Autodesk Inventor part; units mm, degrees
(part 2 of 2)
  spline S387 degree 2 poles (67.0107, -7.6579) (67.1116, -7.5623) (67.7381, -7.0526) knots 0 0 0 1 1 1
  spline S388 degree 2 poles (77.2373, -9.203) (77.7948, -9.5747) (78.0019, -9.8455) knots 0 0 0 1 1 1
  spline S389 degree 2 poles (78.0019, -9.8455) (78.0974, -9.9623) (78.0974, -10.1163) knots 0 0 0 1 1 1
  spline S390 degree 2 poles (78.0974, -10.1163) (78.0974, -10.2119) (78.0231, -10.2862) knots 0 0 0 1 1 1
  spline S391 degree 2 poles (78.0231, -10.2862) (77.9594, -10.3499) (77.8691, -10.3499) knots 0 0 0 1 1 1
  spline S392 degree 2 poles (77.8691, -10.3499) (77.7257, -10.3499) (77.5665, -10.1588) knots 0 0 0 1 1 1
  spline S393 degree 2 poles (77.5665, -10.1588) (77.3222, -9.8189) (77.0673, -9.6331) knots 0 0 0 1 1 1
  spline S394 degree 2 poles (77.0673, -9.6331) (76.8921, -9.9835) (76.5045, -10.1641) knots 0 0 0 1 1 1
  spline S395 degree 2 poles (76.5045, -10.1641) (76.2072, -10.3021) (75.8726, -10.3021) knots 0 0 0 1 1 1
  spline S396 degree 2 poles (75.8726, -10.3021) (75.3895, -10.3021) (75.0974, -10.0951) knots 0 0 0 1 1 1
  spline S397 degree 2 poles (75.0974, -10.0951) (74.8001, -9.8933) (74.8001, -9.5375) knots 0 0 0 1 1 1
  spline S398 degree 2 poles (74.8001, -9.5375) (74.8001, -9.1658) (75.1877, -8.9588) knots 0 0 0 1 1 1
  spline S399 degree 2 poles (75.1877, -8.9588) (75.4691, -8.8048) (75.7983, -8.8048) knots 0 0 0 1 1 1
  spline S400 degree 2 poles (75.7983, -8.8048) (76.3611, -8.8048) (76.7965, -9.0066) knots 0 0 0 1 1 1
  spline S401 degree 2 poles (76.7965, -9.0066) (76.8974, -8.3641) (76.8974, -7.6897) knots 0 0 0 1 1 1
  spline S402 degree 2 poles (76.8974, -7.6897) (76.8974, -6.7712) (76.6638, -6.2455) knots 0 0 0 1 1 1
  spline S403 degree 2 poles (76.6638, -6.2455) (76.4302, -5.7305) (75.9364, -5.7305) knots 0 0 0 1 1 1
  spline S404 degree 2 poles (75.9364, -5.7305) (75.4744, -5.7305) (74.9063, -6.1924) knots 0 0 0 1 1 1
  spline S405 degree 2 poles (74.9063, -6.1924) (74.1842, -6.7765) (73.1965, -7.865) knots 0 0 0 1 1 1
  spline S406 degree 2 poles (73.1965, -7.865) (73.2019, -8.3057) (73.2231, -9.2349) knots 0 0 0 1 1 1
  spline S407 degree 2 poles (73.2231, -9.2349) (73.239, -9.9358) (73.239, -10.0844) knots 0 0 0 1 1 1
  spline S408 degree 2 poles (73.239, -10.0844) (73.239, -10.8119) (72.9948, -10.8119) knots 0 0 0 1 1 1
  spline S409 degree 2 poles (72.9948, -10.8119) (72.7983, -10.8119) (72.7771, -10.5942) knots 0 0 0 1 1 1
  spline S410 degree 2 poles (72.7771, -10.5942) (72.7346, -10.2756) (72.6178, -10.1163) knots 0 0 0 1 1 1
  spline S411 degree 2 poles (72.6178, -10.1163) (72.278, -9.6437) (71.9647, -9.288) knots 0 0 0 1 1 1
  spline S412 degree 2 poles (71.9647, -9.288) (71.8054, -9.5004) (71.6408, -9.6862) knots 0 0 0 1 1 1
  spline S413 degree 2 poles (71.6408, -9.6862) (71.5505, -9.803) (71.4178, -9.803) knots 0 0 0 1 1 1
  spline S414 degree 2 poles (71.4178, -9.803) (71.2319, -9.803) (71.2319, -9.5641) knots 0 0 0 1 1 1
  spline S415 degree 2 poles (71.2319, -9.5641) (71.2319, -9.442) (71.3753, -9.272) knots 0 0 0 1 1 1
  spline S416 degree 2 poles (71.3753, -9.272) (71.9912, -8.5977) (72.3045, -8.157) knots 0 0 0 1 1 1
  spline S417 degree 2 poles (72.3045, -8.157) (72.6921, -7.6048) (72.8939, -7.0685) knots 0 0 0 1 1 1
  spline S418 degree 2 poles (72.8939, -7.0685) (72.9151, -6.7818) (72.9311, -6.4685) knots 0 0 0 1 1 1
  spline S419 degree 2 poles (72.9311, -6.4685) (72.6231, -6.5906) (72.4744, -6.6809) knots 0 0 0 1 1 1
  spline S420 degree 2 poles (72.4744, -6.6809) (72.2992, -6.7712) (72.2514, -6.8136) knots 0 0 0 1 1 1
  spline S421 degree 2 poles (72.2514, -6.8136) (72.1558, -6.9092) (72.0496, -6.9092) knots 0 0 0 1 1 1
  spline S422 degree 2 poles (72.0496, -6.9092) (71.8744, -6.9092) (71.6939, -6.6968) knots 0 0 0 1 1 1
  spline S423 degree 2 poles (71.6939, -6.6968) (71.4921, -6.4579) (71.4921, -6.3092) knots 0 0 0 1 1 1
  spline S424 degree 2 poles (71.4921, -6.3092) (71.4921, -6.1977) (71.5505, -6.1977) knots 0 0 0 1 1 1
  spline S425 degree 2 poles (71.5505, -6.1977) (71.593, -6.1977) (71.6673, -6.272) knots 0 0 0 1 1 1
  spline S426 degree 2 poles (71.6673, -6.272) (71.8426, -6.4526) (72.0072, -6.4526) knots 0 0 0 1 1 1
  spline S427 degree 2 poles (72.0072, -6.4526) (72.1027, -6.4526) (72.1983, -6.4207) knots 0 0 0 1 1 1
  spline S428 degree 2 poles (72.1983, -6.4207) (72.347, -6.3676) (72.947, -6.1287) knots 0 0 0 1 1 1
  spline S429 degree 2 poles (72.947, -6.1287) (72.947, -5.9747) (72.9629, -5.4437) knots 0 0 0 1 1 1
  spline S430 degree 2 poles (72.9629, -5.4437) (72.9735, -5.1198) (72.9735, -4.9765) knots 0 0 0 1 1 1
  spline S431 degree 2 poles (72.9735, -4.9765) (72.9735, -4.6897) (72.8726, -4.5517) knots 0 0 0 1 1 1
  spline S432 degree 2 poles (72.8726, -4.5517) (72.7771, -4.4296) (72.5275, -4.3234) knots 0 0 0 1 1 1
  spline S433 degree 2 poles (72.5275, -4.3234) (72.4532, -4.2915) (72.4532, -4.2384) knots 0 0 0 1 1 1
  spline S434 degree 2 poles (72.4532, -4.2384) (72.4532, -4.1375) (72.6974, -4.1375) knots 0 0 0 1 1 1
  spline S435 degree 2 poles (72.6974, -4.1375) (72.9257, -4.1375) (73.2284, -4.334) knots 0 0 0 1 1 1
  spline S436 degree 2 poles (73.2284, -4.334) (73.616, -4.5889) (73.616, -4.7588) knots 0 0 0 1 1 1
  spline S437 degree 2 poles (73.616, -4.7588) (73.616, -4.8809) (73.5098, -4.9818) knots 0 0 0 1 1 1
  spline S438 degree 2 poles (73.5098, -4.9818) (73.4355, -5.0561) (73.393, -5.2366) knots 0 0 0 1 1 1
  spline S439 degree 2 poles (73.393, -5.2366) (73.3134, -5.5552) (73.3027, -5.98) knots 0 0 0 1 1 1
  spline S440 degree 2 poles (73.3027, -5.98) (73.3824, -5.9375) (73.4355, -5.9375) knots 0 0 0 1 1 1
  spline S441 degree 2 poles (73.4355, -5.9375) (73.5204, -5.9375) (73.6001, -6.0225) knots 0 0 0 1 1 1
  spline S442 degree 2 poles (73.6001, -6.0225) (73.7222, -6.1287) (73.7222, -6.1924) knots 0 0 0 1 1 1
  spline S443 degree 2 poles (73.7222, -6.1924) (73.7222, -6.272) (73.6479, -6.3305) knots 0 0 0 1 1 1
  spline S444 degree 2 poles (73.6479, -6.3305) (73.5576, -6.4101) (73.4939, -6.5375) knots 0 0 0 1 1 1
  spline S445 degree 2 poles (73.4939, -6.5375) (73.3452, -6.803) (73.1965, -7.1694) knots 0 0 0 1 1 1
  line L32 (73.1965, -7.1694) -> (73.1806, -7.4508)
  spline S446 degree 2 poles (73.1806, -7.4508) (74.0886, -6.4951) (74.7257, -6.0066) knots 0 0 0 1 1 1
  spline S447 degree 2 poles (74.7257, -6.0066) (75.4266, -5.4597) (75.8939, -5.4597) knots 0 0 0 1 1 1
  spline S448 degree 2 poles (75.8939, -5.4597) (76.7222, -5.4597) (77.0939, -6.2561) knots 0 0 0 1 1 1
  spline S449 degree 2 poles (77.0939, -6.2561) (77.3806, -6.8349) (77.3806, -7.7641) knots 0 0 0 1 1 1
  spline S450 degree 2 poles (77.3806, -7.7641) (77.3806, -8.4703) (77.2373, -9.203) knots 0 0 0 1 1 1
  spline S451 degree 2 poles (76.6691, -9.3835) (76.1912, -9.1181) (75.724, -9.1181) knots 0 0 0 1 1 1
  spline S452 degree 2 poles (75.724, -9.1181) (75.3948, -9.1181) (75.2089, -9.2561) knots 0 0 0 1 1 1
  spline S453 degree 2 poles (75.2089, -9.2561) (75.0549, -9.3623) (75.0549, -9.5269) knots 0 0 0 1 1 1
  spline S454 degree 2 poles (75.0549, -9.5269) (75.0549, -9.9464) (75.7558, -9.9464) knots 0 0 0 1 1 1
  spline S455 degree 2 poles (75.7558, -9.9464) (76.0638, -9.9464) (76.3187, -9.7924) knots 0 0 0 1 1 1
  spline S456 degree 2 poles (76.3187, -9.7924) (76.5735, -9.6384) (76.6691, -9.3835) knots 0 0 0 1 1 1
  spline S457 degree 2 poles (72.0656, -9.1393) (72.3417, -9.4048) (72.7134, -9.7287) knots 0 0 0 1 1 1
  spline S458 degree 2 poles (72.7134, -9.7287) (72.7877, -9.7924) (72.8355, -9.7924) knots 0 0 0 1 1 1
  spline S459 degree 2 poles (72.8355, -9.7924) (72.8673, -9.7924) (72.8673, -9.7446) knots 0 0 0 1 1 1
  spline S460 degree 2 poles (72.8673, -9.7446) (72.878, -9.357) (72.878, -8.0455) knots 0 0 0 1 1 1
  spline S461 degree 2 poles (72.878, -8.0455) (72.416, -8.6349) (72.0656, -9.1393) knots 0 0 0 1 1 1
  point P0 (40, -23)
  constraints: 2 other
extrude "押し出し9" cut sketch "スケッチ13" against normal blind 0.2
equation "\"d29\" = d28"
